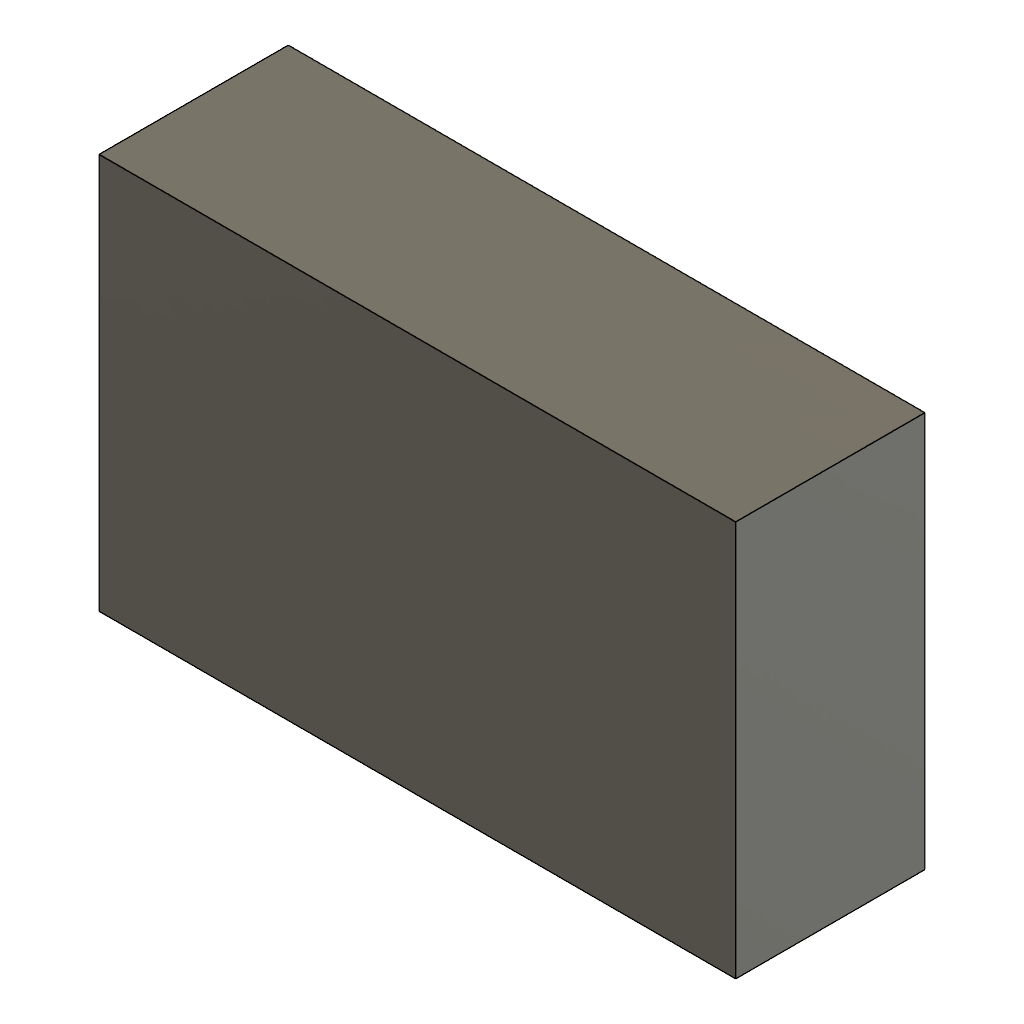
control-before (Autodesk Fusion 360 design; units mm, degrees)
part number: 2026-11-22-21-15-09-801
Autodesk Fusion 360 part; units mm, degrees
sketch "RectangleSketch" plane through (0, 0, 0) normal (0, 0, 1) x (1, 0, 0)
  line L0 (0, 0) -> (37, 0)
  line L1 (37, 0) -> (37, 23)
  line L2 (37, 23) -> (0, 23)
  line L3 (0, 23) -> (0, 0)
  dimension "width_mm" = 37
  dimension "height_mm" = 23
  constraint horizontal L0
  constraint vertical L1
  constraint horizontal L2
  constraint vertical L3
  constraint coincident L0.start L3.end
  measures "width_mm" horizontal distance of L0.start L0.end
  measures "height_mm" vertical distance of L0.start L2.end
extrude "BlindBoss" add sketch "RectangleSketch" along normal blind 11
equation "depth_mm = 11 mm"
